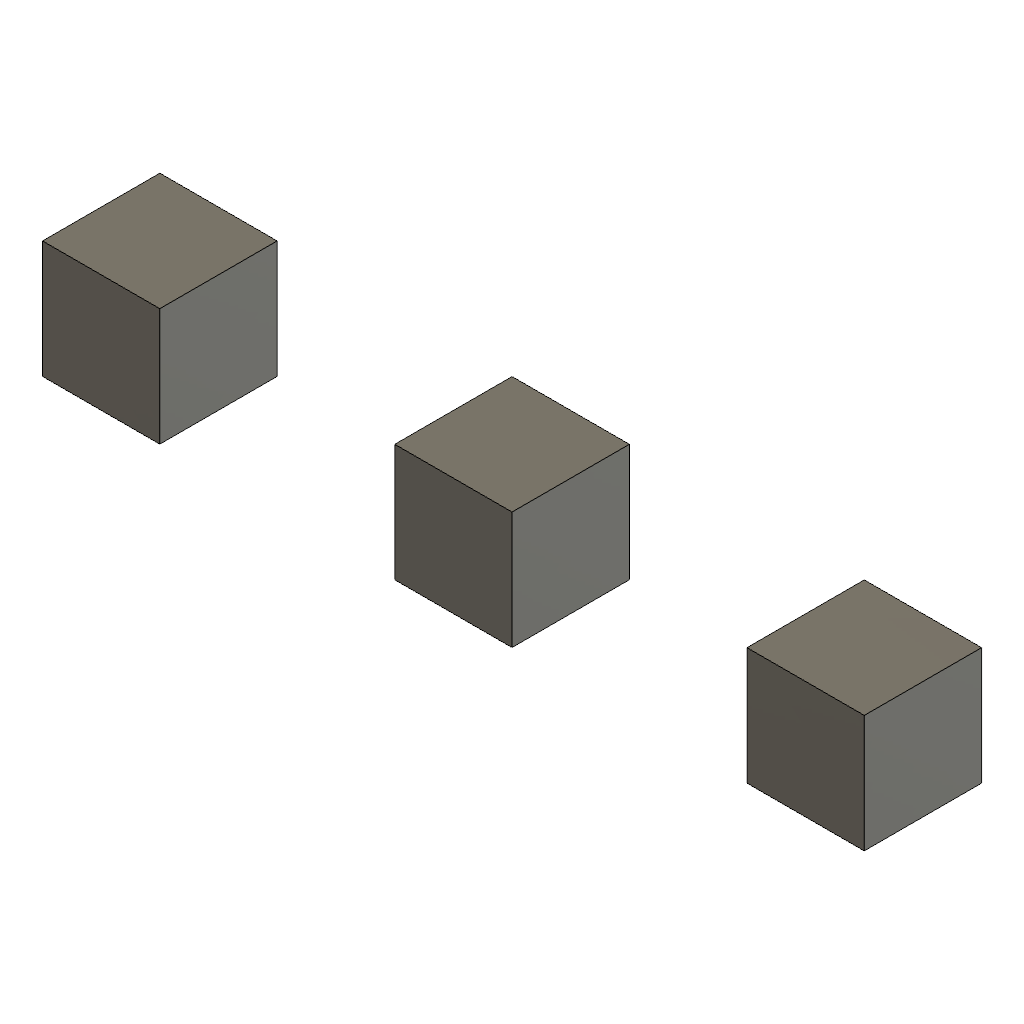
body_negative (Autodesk Fusion 360 design; units mm, degrees)
part number: 2026-10-20-21-45-07-379
Autodesk Fusion 360 part; units mm, degrees
sketch "Sketch1" plane through (0, 0, 0) normal (0, 0, 1) x (1, 0, 0)
  line L0 (10, 0) -> (20, 0)
  line L1 (20, 0) -> (20, 10)
  line L2 (20, 10) -> (10, 10)
  line L3 (10, 10) -> (10, 0)
extrude "SeedFeature0" add sketch "Sketch1" along normal blind 10 makes body 1
pattern_linear "ProbeRectangularPattern" count 3 spacing 30 along (-1, 0, 0) of bodies 1 makes body 2 at (-20, 6.6667, 3.3333) makes body 3 at (-50, 6.6667, 3.3333)
named bodies: "SeedBody0", "SeedBody0 (1)", "SeedBody0 (2)"
